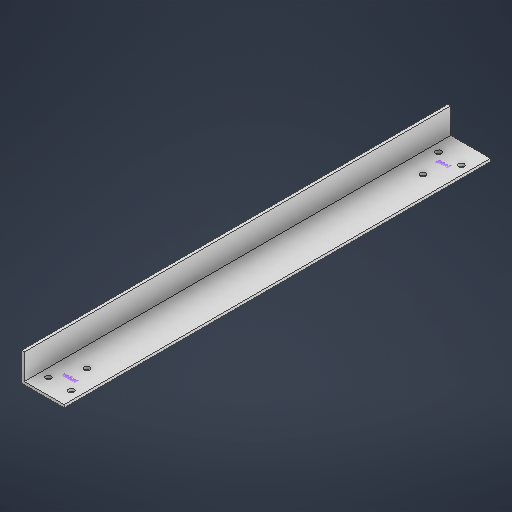
# Autodesk Inventor part: 1_1_2_1_profile_L_D
Saved by Autodesk Inventor 2026 (Build 300175000, 175)
## iProperties
Created: 2025-05-06
Part Number: 1_1_2_1_profile_L_D
Material: Generic
Document SubType Name: Modeling
Designer: remg9
Density: 1 g/cm^3
Appearance: Default
Author: remg9
Autodesk Inventor part; units mm, degrees
ref_plane "YZ Plane" through (0, 0, 0) normal (1, 0, 0) x (0, 1, 0)
ref_plane "XZ Plane" through (0, 0, 0) normal (0, 1, 0) x (-1, 0, 0)
ref_plane "XY Plane" through (0, 0, 0) normal (0, 0, 1) x (1, 0, 0)
sketch "Sketch1" plane through (0, 0, 0) normal (0, 0, 1) x (1, 0, 0)
  line L0 (0, 0) -> (0, 20)
  line L1 (0, 20) -> (2, 20)
  line L2 (2, 20) -> (2, 2)
  line L3 (2, 2) -> (30, 2)
  line L4 (30, 2) -> (30, 0)
  line L5 (30, 0) -> (0, 0)
  dimension "d0" = 2
  dimension "d1" = 30
  dimension "d2" = 2
  dimension "d3" = 20
  constraints: 12 end point, 5 perpendicular, 1 vertical
  measures "d0" distance of L3.end L4.end
  measures "d1" distance of L4.end L0.start
  measures "d2" distance of L0.end L1.end
  measures "d3" distance of L0.start L0.end
extrude "Extrusion1" add sketch "Sketch1" along normal blind 300
sketch "Sketch2" plane through (2, 2, 0) normal (0, 1, 0) x (1, 0, 0)
  line L0 (28, 0) -> (28, -300) projected
  line L1 (0, 0) -> (0, -300) projected
  line L2 (6, -289) -> (22, -289) construction
  line L3 (28, -300) -> (0, -300) projected
  line L4 (6, -14.5) -> (22, -14.5) construction
  line L5 (28, 0) -> (0, 0) projected
  point P0 (-2, 0)
  point P1 (14, -270)
  point P2 (14, -289)
  point P3 (14, -33.5)
  dimension "d6" = 14
  dimension "d7" = 6
  dimension "d8" = 6
  dimension "d9" = 19
  dimension "d10" = 11
  dimension "d11" = 6
  dimension "d12" = 6
  dimension "d13" = 19
  dimension "d14" = 14
  dimension "d15" = 14.5
  constraints: 4 end point, 2 horizontal, 1 midpoint
  measures "d6" distance from line of L0 point (14, -270)
  measures "d7" distance from line of L0 L2.end
  measures "d8" distance from line of L1 L2.start
  measures "d9" distance of point (14, -289) point (14, -270)
  measures "d10" distance between parallel lines of L3 L2
  measures "d11" distance from line of L0 L4.end
  measures "d12" distance from line of L1 L4.start
  measures "d13" distance from line of point (14, -33.5) L4
  measures "d14" distance from line of L0 point (14, -33.5)
  measures "d15" distance between parallel lines of L5 L4
hole "Hole1" at (8, 2, 289) at (24, 2, 289) at (16, 2, 270) at (8, 2, 14.5) at (24, 2, 14.5) at (16, 2, 33.5) direction (0, -1, 0) diameter 4 end through all
sketch "Sketch3" plane through (2, 2, 0) normal (0, 1, 0) x (1, 0, 0)
  line L0 (10.6952, -18.1448) -> (19.0266, -18.1448) construction
  line L1 (19.0266, -18.1448) -> (19.0266, -21.9314) construction
  line L2 (19.0266, -21.9314) -> (10.6952, -21.9314) construction
  line L3 (10.6952, -21.9314) -> (10.6952, -18.1448) construction
  line L4 (9.0023, -279.9442) -> (18.7835, -279.9442) construction
  line L5 (18.7835, -279.9442) -> (18.7835, -283.1923) construction
  line L6 (18.7835, -283.1923) -> (9.0023, -283.1923) construction
  line L7 (9.0023, -283.1923) -> (9.0023, -279.9442) construction
  point P0 (-2, 0)
  dimension "d0" = 2
  dimension "d1" = 30
  dimension "d2" = 2
  dimension "d3" = 20
  constraints: 4 other
body "Solid1"
